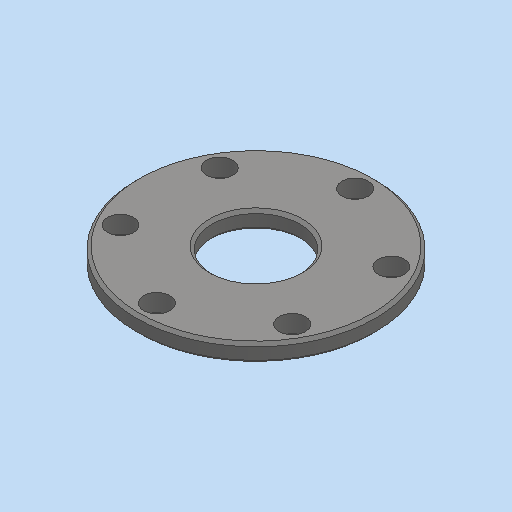
# Autodesk Inventor part: MM0948AN100_G01_127
Saved by Autodesk Inventor 2023.3 (Build 273359000, 359)
## iProperties
Created: 2023-03-23
Part Number: MM0948AN100_G01_127
Material: 1.2379 X155CrVMo12-1
Description: =<RBPARTNOTITLE2>
Document SubType Name: Modeling
Designer: ric7an
Mass: 24.3378 g
Surface Area: 27.7543 cm^2
Volume: 3.10036 cm^3
Density: 7.85 g/cm^3
Appearance: Stahl - rostfrei AnP
AnP_Kategorie: 1
AnP_Material: =<Material>
MaxAbmaße: 3 x 41 x 41 (FM)
AnP_TemplVers: 20200821
RBDOCUMENTTYPE: DRF
RBDOCUMENTVERSION: 00
RBDRAWINGMAINSCALE: 1:1
RBDRAWINGMISSINGSPEC: --
RBDRAWINGVOLUME: --
RBDSV1: 0850
RBGBEDGESIN1: +0,5
RBGBEDGESIN2: +0,2
RBGBEDGESOUT1: -0,3
RBGBEDGESOUT2: -0,1
RBMATERIAL: =<Material>
RBMATMEETS: --
RBMATNO: =<Part Number>
RBPARTMADEOF: Ø41 x 3 (FM)
RBPARTNO: SIEHE MNR
RBPARTNOTITLE1: manufactured part
RBPARTNOTITLE2: Anfertigungsteil
RBPARTSAFETYINDICATOR: --
RBSURFACE: --
RBSURFACE2: --
RBZEDGESNORM: ISO13715:2002-06
RBZGENDIMCLASS: m
RBZGENDIMNORM: ISO 2768-1:1989-11
RBZGENGEOCLASS: H
RBZGENGEONORM: ISO 2768-2:1989-11
RBZSURFACENORM: ISO13D2:2002-02
RBZTOLERANCENORM: ISO 14405-1:2010-12
AnP_Kommentar_aktuell: =<Comments>
AnP_Material_aktuell: =<Material>
Author: FH/Wi
Keywords: =<RBPARTMADEOF>
Comments: =<RBSURFACE2>
Revision Number: 01
Autodesk Inventor part; units mm, degrees
ref_plane "YZ Plane" through (0, 0, 0) normal (1, 0, 0) x (0, 1, 0)
ref_plane "XZ Plane" through (0, 0, 0) normal (0, 1, 0) x (-1, 0, 0)
ref_plane "XY Plane" through (0, 0, 0) normal (0, 0, 1) x (1, 0, 0)
sketch "Skizze1" plane through (0, 0, 0) normal (0, 0, 1) x (1, 0, 0)
  circle A0 centre (0, 0) radius 20.5
  dimension "d0" = 41
  constraints: 1 centre point, 1 coincident
  measures "d0" diameter of A0
extrude "Extrusion1" add sketch "Skizze1" along normal blind 3
sketch "Skizze2" plane through (0, 0, 3) normal (0, 0, 1) x (1, 0, 0)
  line L0 (0, 28.7) -> (0, -28.7) projected
  line L1 (-28.7, 0) -> (28.7, 0) projected
  line L2 (-14.7224, -8.5) -> (0, 0) construction
  line L3 (0, 0) -> (14.7224, -8.5) construction
  point P0 (0, 17)
  dimension "d3" = 17
  dimension "d4" = 17
  dimension "d5" = 17
  dimension "d6" = 120
  dimension "d7" = 120
  constraints: 4 end point, 1 point on line
  measures "d3" distance from line of L1 point (0, 17)
  measures "d4" distance of L2.start L2.end
  measures "d5" distance of L2.end L3.end
  measures "d6" angle of L3 L0
  measures "d7" angle of L3 L2
hole "Bohrung1" at (0, 17, 3) at (14.7224, -8.5, 3) at (-14.7224, -8.5, 3) direction (0, 0, -1) diameter 4.5 end through all clearance for "Inbusschraube ISO 4762  versenkt" size "M4" standard "ISO"
sketch "Skizze3" plane through (0, 0, 3) normal (0, 0, 1) x (1, 0, 0)
  point P0 (0, 0)
  point P1 (0, 0)
  constraints: 1 coincident
hole "Bohrung2" at (0, 0, 3) direction (0, 0, -1) diameter 15 end through all
chamfer "Fase1" distance 0.5 angle 45 4 edges at (0, 7.5, 0) (0, 7.5, 3) (-20.5, 0, 0) (-20.5, 0, 3)
pattern_circular "Runde Anordnung1" count 2 over 60 about axis through (0, 0, -10) along (0, 0, 1) of "Bohrung1"
equation "\"d4\" = d3"
equation "\"d5\" = d3"
equation "\"d7\" = d6"
